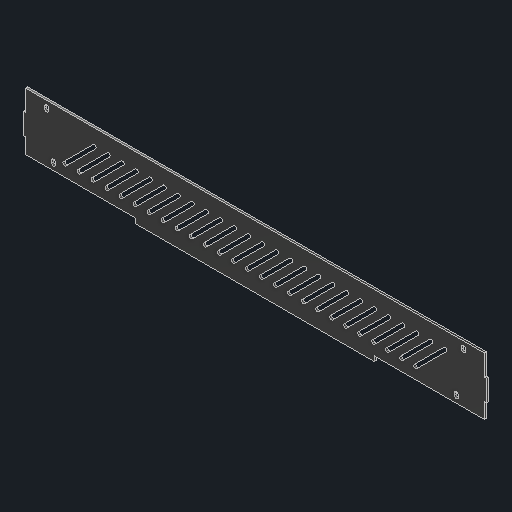
# Autodesk Inventor part: PowerBoxLengthFace
Saved by Autodesk Inventor 2027.1 (Build 311270010, 270A)
## iProperties
Created: 2026-10-13
Part Number: PowerBoxLengthFace
Material: MDF Medium Density Fiberboard
Document SubType Name: Modeling
Designer: SDS Scholar
Density: 0.8 g/cm^3
Appearance: Glossy - Black
Mass: 121.059 g
Surface Area: 1052.27 cm^2
Volume: 151.324 cm^3
Author: SDS Scholar
Autodesk Inventor part; units mm, degrees
ref_plane "YZ Plane" through (0, 0, 0) normal (1, 0, 0) x (0, 1, 0)
ref_plane "XZ Plane" through (0, 0, 0) normal (0, 1, 0) x (-1, 0, 0)
ref_plane "XY Plane" through (0, 0, 0) normal (0, 0, 1) x (1, 0, 0)
sketch "Sketch1" plane through (0, 0, 0) normal (0, 0, 1) x (1, 0, 0)
  line L0 (-330, 44.5) -> (330, 44.5)
  line L1 (330, 44.5) -> (330, -44.5)
  line L2 (330, -44.5) -> (-330, -44.5)
  line L3 (-330, -44.5) -> (-330, 44.5)
  point P0 (0, 0)
  point P1 (330, 0)
  point P2 (0, 44.5)
  dimension "d0" = 660
  dimension "d1" = 89
  constraints: 8 end point, 2 midpoint, 2 parallel, 1 horizontal, 1 horizontal alignment, 1 perpendicular, 1 vertical alignment
  measures "d0" distance of L0.start L0.end
  measures "d1" distance of L0.end L1.end
extrude "Extrusion1" add sketch "Sketch1" along normal blind 3
sketch "Sketch2" plane through (0, 0, 0) normal (0, 0, -1) x (-1, 0, 0)
  line L0 (-313.2342, 61.5305) -> (316.7658, 61.5305)
  line L1 (-310.2342, 64.5305) -> (313.7658, 64.5305)
  line L2 (316.7658, 61.5305) -> (316.7658, 64.5305)
  line L3 (316.7658, 64.5305) -> (236.7658, 64.5305)
  line L4 (236.7658, 64.5305) -> (236.7658, 61.5305)
  line L5 (236.7658, 61.5305) -> (316.7658, 61.5305)
  line L6 (316.7658, 61.5305) -> (-313.2342, 61.5305)
  line L7 (236.7658, 64.5305) -> (236.7658, 61.5305)
  line L8 (236.7658, 61.5305) -> (156.4658, 61.5305)
  line L9 (156.4658, 61.5305) -> (156.4658, 64.5305)
  line L10 (156.4658, 64.5305) -> (236.7658, 64.5305)
  line L11 (156.4658, 64.5305) -> (156.4658, 61.5305)
  line L12 (156.4658, 61.5305) -> (76.4658, 61.5305)
  line L13 (76.4658, 61.5305) -> (76.4658, 64.5305)
  line L14 (76.4658, 64.5305) -> (156.4658, 64.5305)
  line L15 (76.4658, 61.5305) -> (76.4658, 64.5305)
  line L16 (76.4658, 64.5305) -> (-3.8342, 64.5305)
  line L17 (-3.8342, 64.5305) -> (-3.8342, 61.5305)
  line L18 (-3.8342, 61.5305) -> (76.4658, 61.5305)
  line L19 (-3.8342, 64.5305) -> (-3.8342, 61.5305)
  line L20 (-3.8342, 61.5305) -> (-83.8342, 61.5305)
  line L21 (-83.8342, 61.5305) -> (-83.8342, 64.5305)
  line L22 (-83.8342, 64.5305) -> (-3.8342, 64.5305)
  line L23 (-83.8342, 64.5305) -> (-83.8342, 61.5305)
  line L24 (-83.8342, 61.5305) -> (-164.1342, 61.5305)
  line L25 (-164.1342, 61.5305) -> (-164.1342, 64.5305)
  line L26 (-164.1342, 64.5305) -> (-83.8342, 64.5305)
  line L27 (-164.1342, 64.5305) -> (-164.1342, 61.5305)
  line L28 (-164.1342, 61.5305) -> (-244.1342, 61.5305)
  line L29 (-244.1342, 61.5305) -> (-244.1342, 64.5305)
  line L30 (-244.1342, 64.5305) -> (-164.1342, 64.5305)
  line L31 (-244.1342, 64.5305) -> (-244.1342, 61.5305)
  line L32 (-244.1342, 61.5305) -> (-313.2342, 61.5305)
  line L33 (-313.2342, 61.5305) -> (-313.2342, 64.5305)
  line L34 (-313.2342, 64.5305) -> (-244.1342, 64.5305)
  line L35 (313.7658, 64.5305) -> (316.7658, 64.5305)
  line L36 (-313.2342, 61.5305) -> (-313.2342, 64.5305)
  line L37 (-310.2342, 64.5305) -> (-313.2342, 64.5305)
  line L38 (-330, 44.5) -> (-330, 47.5)
  line L39 (315, 39.5) -> (315, 42.5)
  line L40 (-330, 47.5) -> (300, 47.5)
  line L41 (-330, 47.5) -> (330, 47.5)
  line L42 (330, 47.5) -> (330, -44.5)
  line L43 (330, -44.5) -> (-330, -44.5)
  line L44 (-330, -44.5) -> (-330, 47.5)
  line L45 (-327, 44.5) -> (327, 44.5)
  line L46 (327, 44.5) -> (327, -41.5)
  line L47 (327, -41.5) -> (-327, -41.5)
  line L48 (-327, -41.5) -> (-327, 44.5)
  line L49 (330, 47.5) -> (249.7, 47.5)
  line L50 (249.7, 47.5) -> (249.7, 44.5)
  line L51 (249.7, 44.5) -> (330, 44.5)
  line L52 (330, 44.5) -> (330, 47.5)
  line L53 (249.7, 44.5) -> (169.7, 44.5)
  line L54 (169.7, 44.5) -> (169.7, 47.5)
  line L55 (169.7, 47.5) -> (249.7, 47.5)
  line L56 (249.7, 47.5) -> (249.7, 44.5)
  line L57 (169.7, 47.5) -> (89.4, 47.5)
  line L58 (89.4, 47.5) -> (89.4, 44.5)
  line L59 (89.4, 44.5) -> (169.7, 44.5)
  line L60 (169.7, 44.5) -> (169.7, 47.5)
  line L61 (89.4, 44.5) -> (9.4, 44.5)
  line L62 (9.4, 44.5) -> (9.4, 47.5)
  line L63 (9.4, 47.5) -> (89.4, 47.5)
  line L64 (89.4, 47.5) -> (89.4, 44.5)
  line L65 (9.4, 44.5) -> (-70.9, 44.5)
  line L66 (-70.9, 44.5) -> (-70.9, 47.5)
  line L67 (-70.9, 47.5) -> (9.4, 47.5)
  line L68 (9.4, 47.5) -> (9.4, 44.5)
  line L69 (-70.9, 44.5) -> (-150.9, 44.5)
  line L70 (-150.9, 44.5) -> (-150.9, 47.5)
  line L71 (-150.9, 47.5) -> (-70.9, 47.5)
  line L72 (-70.9, 47.5) -> (-70.9, 44.5)
  line L73 (-150.9, 44.5) -> (-231.2, 44.5)
  line L74 (-231.2, 44.5) -> (-231.2, 47.5)
  line L75 (-231.2, 47.5) -> (-150.9, 47.5)
  line L76 (-150.9, 47.5) -> (-150.9, 44.5)
  line L77 (-231.2, 44.5) -> (-330, 44.5)
  line L78 (-330, 44.5) -> (-330, 47.5)
  line L79 (-330, 47.5) -> (-231.2, 47.5)
  line L80 (-231.2, 47.5) -> (-231.2, 44.5)
  line L81 (-429.1643, 55.2975) -> (-429.1643, 52.2975)
  line L82 (-429.1643, 52.2975) -> (-429.1643, -26.7025)
  line L83 (-429.1643, -26.7025) -> (-429.1643, 52.2975)
  line L84 (-426.1643, -23.7025) -> (-426.1643, 52.2975)
  line L85 (-429.1643, 52.2975) -> (-426.1643, 52.2975)
  line L86 (-426.1643, 52.2975) -> (-426.1643, 21.9975)
  line L87 (-426.1643, 21.9975) -> (-429.1643, 21.9975)
  line L88 (-429.1643, 21.9975) -> (-429.1643, 52.2975)
  line L89 (-426.1643, 21.9975) -> (-429.1643, 21.9975)
  line L90 (-429.1643, 21.9975) -> (-429.1643, -8.0025)
  line L91 (-429.1643, -8.0025) -> (-426.1643, -8.0025)
  line L92 (-426.1643, -8.0025) -> (-426.1643, 21.9975)
  line L93 (-426.1643, -8.0025) -> (-429.1643, -8.0025)
  line L94 (-429.1643, -8.0025) -> (-429.1643, -26.7025)
  line L95 (-429.1643, -26.7025) -> (-426.1643, -26.7025)
  line L96 (-426.1643, -26.7025) -> (-426.1643, -8.0025)
  line L97 (-429.1643, 55.2975) -> (-426.1643, 55.2975)
  line L98 (-426.1643, 55.2975) -> (-426.1643, 52.2975)
  line L99 (-426.1643, 52.2975) -> (-429.1643, 52.2975)
  line L100 (-429.1643, 52.2975) -> (-429.1643, 55.2975)
  line L101 (-330, 44.5) -> (-327, 44.5)
  line L102 (-327, 44.5) -> (-327, 14.5)
  line L103 (-327, 14.5) -> (-330, 14.5)
  line L104 (-330, 14.5) -> (-330, 44.5)
  line L105 (-327, 14.5) -> (-330, 14.5)
  line L106 (-330, 14.5) -> (-330, -15.8)
  line L107 (-330, -15.8) -> (-327, -15.8)
  line L108 (-327, -15.8) -> (-327, 14.5)
  line L109 (-330, -15.8) -> (-327, -15.8)
  line L110 (-327, -15.8) -> (-327, -44.5)
  line L111 (-327, -44.5) -> (-330, -44.5)
  line L112 (-330, -44.5) -> (-330, -15.8)
  line L113 (327, 44.5) -> (330, 44.5)
  line L114 (330, 44.5) -> (330, 14.5)
  line L115 (330, 14.5) -> (327, 14.5)
  line L116 (327, 14.5) -> (327, 44.5)
  line L117 (327, 14.5) -> (330, 14.5)
  line L118 (330, 14.5) -> (330, -15.8)
  line L119 (330, -15.8) -> (327, -15.8)
  line L120 (327, -15.8) -> (327, 14.5)
  line L121 (327, -15.8) -> (330, -15.8)
  line L122 (330, -15.8) -> (330, -44.5)
  line L123 (330, -44.5) -> (327, -44.5)
  line L124 (327, -44.5) -> (327, -15.8)
  point P0 (0, 0)
  point P1 (1.7658, 32.3371)
  point P2 (-310.2342, 64.5305)
  point P3 (327, 44.5)
  point P4 (249.7, 47.5)
  point P5 (89.4, 47.5)
  point P6 (169.7, 44.5)
  point P7 (169.7, 47.5)
  point P8 (-70.9, 47.5)
  point P9 (-70.9, 44.5)
  point P10 (9.4, 44.5)
  point P11 (9.4, 47.5)
  point P12 (-231.2, 47.5)
  point P13 (-150.9, 44.5)
  point P14 (-289.1643, -8.0025)
  point P15 (327, -41.5)
  point P16 (327, 44.5)
  point P17 (-330, 14.5)
  point P18 (-327, 44.5)
  point P19 (-330, 44.5)
  point P20 (280, 47.5)
  point P21 (-277, 44.5)
  point P22 (-280, 44.5)
  dimension "d4" = 3
  dimension "d5" = 80
  dimension "d6" = 80.3
  dimension "d7" = 80
  dimension "d8" = 80.3
  dimension "d9" = 80
  dimension "d10" = 80.3
  dimension "d11" = 80
  dimension "d14" = 3
  dimension "d15" = 80.3
  dimension "d16" = 80
  dimension "d17" = 80.3
  dimension "d18" = 80
  dimension "d19" = 80.3
  dimension "d20" = 80
  dimension "d21" = 80.3
  dimension "d24" = 3
  dimension "d25" = 30.3
  dimension "d26" = 30
  dimension "d27" = 30
  dimension "d28" = 30.3
  dimension "d29" = 30
  dimension "d30" = 30.3
  constraints: 250 end point, 56 parallel, 28 perpendicular, 23 point on line, 20 horizontal, 3 other
  measures "d4" distance between parallel lines of L0 L1
  measures "d5" distance of L4.start L3.start
  measures "d6" distance of L7.end L9.start
  measures "d7" distance of L11.end L12.end
  measures "d8" distance of L17.start L15.end
  measures "d9" distance of L19.end L20.end
  measures "d10" distance of L24.start L24.end
  measures "d11" distance of L27.end L29.start
  measures "d14" distance between parallel lines of L44 L48
  measures "d15" distance of L51.end L50.end
  measures "d16" distance of L54.end L55.end
  measures "d17" distance of L59.end L58.end
  measures "d18" distance of L62.end L63.end
  measures "d19" distance of L66.end L67.end
  measures "d20" distance of L70.end L71.end
  measures "d21" distance of L74.end L75.end
  measures "d24" distance between parallel lines of L83 L84
  measures "d25" distance of L86.start L92.end
  measures "d26" distance of L91.start L89.end
  measures "d27" distance of L101.end L102.end
  measures "d28" distance of L106.end L105.end
  measures "d29" distance of L113.end L114.end
  measures "d30" distance of L117.end L118.end
extrude "Extrusion3" cut sketch "Sketch2" against normal blind 80.3 contours L77 L48 L103 L44 | L107 L48 L110 L43 L44 | L124 L46 L119 L42 L43 | L46 L51 L42 L115
sketch "Sketch3" plane through (0, 0, 0) normal (0, 0, -1) x (-1, 0, 0)
  line L0 (291.2132, -21.2132) -> (248.7868, 21.2132) construction
  line L1 (292.981, -19.4454) -> (250.5546, 22.981)
  line L2 (247.019, 19.4454) -> (289.4454, -22.981)
  arc A0 (289.4454, -22.981) -> (292.981, -19.4454) centre (291.2132, -21.2132) ccw
  arc A1 (250.5546, 22.981) -> (247.019, 19.4454) centre (248.7868, 21.2132) ccw
  line L3 (-315, 0) -> (315, 0)
  line L4 (227.019, 19.4454) -> (269.4454, -22.981)
  line L5 (272.981, -19.4454) -> (230.5546, 22.981)
  arc A2 (269.4454, -22.981) -> (272.981, -19.4454) centre (271.2132, -21.2132) ccw
  arc A3 (230.5546, 22.981) -> (227.019, 19.4454) centre (228.7868, 21.2132) ccw
  line L6 (271.2132, -21.2132) -> (228.7868, 21.2132) construction
  line L7 (207.019, 19.4454) -> (249.4454, -22.981)
  line L8 (252.981, -19.4454) -> (210.5546, 22.981)
  arc A4 (249.4454, -22.981) -> (252.981, -19.4454) centre (251.2132, -21.2132) ccw
  arc A5 (210.5546, 22.981) -> (207.019, 19.4454) centre (208.7868, 21.2132) ccw
  line L9 (251.2132, -21.2132) -> (208.7868, 21.2132) construction
  line L10 (187.019, 19.4454) -> (229.4454, -22.981)
  line L11 (232.981, -19.4454) -> (190.5546, 22.981)
  arc A6 (229.4454, -22.981) -> (232.981, -19.4454) centre (231.2132, -21.2132) ccw
  arc A7 (190.5546, 22.981) -> (187.019, 19.4454) centre (188.7868, 21.2132) ccw
  line L12 (231.2132, -21.2132) -> (188.7868, 21.2132) construction
  line L13 (167.019, 19.4454) -> (209.4454, -22.981)
  line L14 (212.981, -19.4454) -> (170.5546, 22.981)
  arc A8 (209.4454, -22.981) -> (212.981, -19.4454) centre (211.2132, -21.2132) ccw
  arc A9 (170.5546, 22.981) -> (167.019, 19.4454) centre (168.7868, 21.2132) ccw
  line L15 (211.2132, -21.2132) -> (168.7868, 21.2132) construction
  line L16 (147.019, 19.4454) -> (189.4454, -22.981)
  line L17 (192.981, -19.4454) -> (150.5546, 22.981)
  arc A10 (189.4454, -22.981) -> (192.981, -19.4454) centre (191.2132, -21.2132) ccw
  arc A11 (150.5546, 22.981) -> (147.019, 19.4454) centre (148.7868, 21.2132) ccw
  line L18 (191.2132, -21.2132) -> (148.7868, 21.2132) construction
  line L19 (127.019, 19.4454) -> (169.4454, -22.981)
  line L20 (172.981, -19.4454) -> (130.5546, 22.981)
  arc A12 (169.4454, -22.981) -> (172.981, -19.4454) centre (171.2132, -21.2132) ccw
  arc A13 (130.5546, 22.981) -> (127.019, 19.4454) centre (128.7868, 21.2132) ccw
  line L21 (171.2132, -21.2132) -> (128.7868, 21.2132) construction
  line L22 (107.019, 19.4454) -> (149.4454, -22.981)
  line L23 (152.981, -19.4454) -> (110.5546, 22.981)
  arc A14 (149.4454, -22.981) -> (152.981, -19.4454) centre (151.2132, -21.2132) ccw
  arc A15 (110.5546, 22.981) -> (107.019, 19.4454) centre (108.7868, 21.2132) ccw
  line L24 (151.2132, -21.2132) -> (108.7868, 21.2132) construction
  line L25 (87.019, 19.4454) -> (129.4454, -22.981)
  line L26 (132.981, -19.4454) -> (90.5546, 22.981)
  arc A16 (129.4454, -22.981) -> (132.981, -19.4454) centre (131.2132, -21.2132) ccw
  arc A17 (90.5546, 22.981) -> (87.019, 19.4454) centre (88.7868, 21.2132) ccw
  line L27 (131.2132, -21.2132) -> (88.7868, 21.2132) construction
  line L28 (67.019, 19.4454) -> (109.4454, -22.981)
  line L29 (112.981, -19.4454) -> (70.5546, 22.981)
  arc A18 (109.4454, -22.981) -> (112.981, -19.4454) centre (111.2132, -21.2132) ccw
  arc A19 (70.5546, 22.981) -> (67.019, 19.4454) centre (68.7868, 21.2132) ccw
  line L30 (111.2132, -21.2132) -> (68.7868, 21.2132) construction
  line L31 (47.019, 19.4454) -> (89.4454, -22.981)
  line L32 (92.981, -19.4454) -> (50.5546, 22.981)
  arc A20 (89.4454, -22.981) -> (92.981, -19.4454) centre (91.2132, -21.2132) ccw
  arc A21 (50.5546, 22.981) -> (47.019, 19.4454) centre (48.7868, 21.2132) ccw
  line L33 (91.2132, -21.2132) -> (48.7868, 21.2132) construction
  line L34 (27.019, 19.4454) -> (69.4454, -22.981)
  line L35 (72.981, -19.4454) -> (30.5546, 22.981)
  arc A22 (69.4454, -22.981) -> (72.981, -19.4454) centre (71.2132, -21.2132) ccw
  arc A23 (30.5546, 22.981) -> (27.019, 19.4454) centre (28.7868, 21.2132) ccw
  line L36 (71.2132, -21.2132) -> (28.7868, 21.2132) construction
  line L37 (7.019, 19.4454) -> (49.4454, -22.981)
  line L38 (52.981, -19.4454) -> (10.5546, 22.981)
  arc A24 (49.4454, -22.981) -> (52.981, -19.4454) centre (51.2132, -21.2132) ccw
  arc A25 (10.5546, 22.981) -> (7.019, 19.4454) centre (8.7868, 21.2132) ccw
  line L39 (51.2132, -21.2132) -> (8.7868, 21.2132) construction
  line L40 (-12.981, 19.4454) -> (29.4454, -22.981)
  line L41 (32.981, -19.4454) -> (-9.4454, 22.981)
  arc A26 (29.4454, -22.981) -> (32.981, -19.4454) centre (31.2132, -21.2132) ccw
  arc A27 (-9.4454, 22.981) -> (-12.981, 19.4454) centre (-11.2132, 21.2132) ccw
  line L42 (31.2132, -21.2132) -> (-11.2132, 21.2132) construction
  line L43 (-32.981, 19.4454) -> (9.4454, -22.981)
  line L44 (12.981, -19.4454) -> (-29.4454, 22.981)
  arc A28 (9.4454, -22.981) -> (12.981, -19.4454) centre (11.2132, -21.2132) ccw
  arc A29 (-29.4454, 22.981) -> (-32.981, 19.4454) centre (-31.2132, 21.2132) ccw
  line L45 (11.2132, -21.2132) -> (-31.2132, 21.2132) construction
  line L46 (-52.981, 19.4454) -> (-10.5546, -22.981)
  line L47 (-7.019, -19.4454) -> (-49.4454, 22.981)
  arc A30 (-10.5546, -22.981) -> (-7.019, -19.4454) centre (-8.7868, -21.2132) ccw
  arc A31 (-49.4454, 22.981) -> (-52.981, 19.4454) centre (-51.2132, 21.2132) ccw
  line L48 (-8.7868, -21.2132) -> (-51.2132, 21.2132) construction
  line L49 (-72.981, 19.4454) -> (-30.5546, -22.981)
  line L50 (-27.019, -19.4454) -> (-69.4454, 22.981)
  arc A32 (-30.5546, -22.981) -> (-27.019, -19.4454) centre (-28.7868, -21.2132) ccw
  arc A33 (-69.4454, 22.981) -> (-72.981, 19.4454) centre (-71.2132, 21.2132) ccw
  line L51 (-28.7868, -21.2132) -> (-71.2132, 21.2132) construction
  line L52 (-92.981, 19.4454) -> (-50.5546, -22.981)
  line L53 (-47.019, -19.4454) -> (-89.4454, 22.981)
  arc A34 (-50.5546, -22.981) -> (-47.019, -19.4454) centre (-48.7868, -21.2132) ccw
  arc A35 (-89.4454, 22.981) -> (-92.981, 19.4454) centre (-91.2132, 21.2132) ccw
  line L54 (-48.7868, -21.2132) -> (-91.2132, 21.2132) construction
  line L55 (-112.981, 19.4454) -> (-70.5546, -22.981)
  line L56 (-67.019, -19.4454) -> (-109.4454, 22.981)
  arc A36 (-70.5546, -22.981) -> (-67.019, -19.4454) centre (-68.7868, -21.2132) ccw
  arc A37 (-109.4454, 22.981) -> (-112.981, 19.4454) centre (-111.2132, 21.2132) ccw
  line L57 (-68.7868, -21.2132) -> (-111.2132, 21.2132) construction
  line L58 (-132.981, 19.4454) -> (-90.5546, -22.981)
  line L59 (-87.019, -19.4454) -> (-129.4454, 22.981)
  arc A38 (-90.5546, -22.981) -> (-87.019, -19.4454) centre (-88.7868, -21.2132) ccw
  arc A39 (-129.4454, 22.981) -> (-132.981, 19.4454) centre (-131.2132, 21.2132) ccw
  line L60 (-88.7868, -21.2132) -> (-131.2132, 21.2132) construction
  line L61 (-152.981, 19.4454) -> (-110.5546, -22.981)
  line L62 (-107.019, -19.4454) -> (-149.4454, 22.981)
  arc A40 (-110.5546, -22.981) -> (-107.019, -19.4454) centre (-108.7868, -21.2132) ccw
  arc A41 (-149.4454, 22.981) -> (-152.981, 19.4454) centre (-151.2132, 21.2132) ccw
  line L63 (-108.7868, -21.2132) -> (-151.2132, 21.2132) construction
  line L64 (-172.981, 19.4454) -> (-130.5546, -22.981)
  line L65 (-127.019, -19.4454) -> (-169.4454, 22.981)
  arc A42 (-130.5546, -22.981) -> (-127.019, -19.4454) centre (-128.7868, -21.2132) ccw
  arc A43 (-169.4454, 22.981) -> (-172.981, 19.4454) centre (-171.2132, 21.2132) ccw
  line L66 (-128.7868, -21.2132) -> (-171.2132, 21.2132) construction
  line L67 (-192.981, 19.4454) -> (-150.5546, -22.981)
  line L68 (-147.019, -19.4454) -> (-189.4454, 22.981)
  arc A44 (-150.5546, -22.981) -> (-147.019, -19.4454) centre (-148.7868, -21.2132) ccw
  arc A45 (-189.4454, 22.981) -> (-192.981, 19.4454) centre (-191.2132, 21.2132) ccw
  line L69 (-148.7868, -21.2132) -> (-191.2132, 21.2132) construction
  line L70 (-212.981, 19.4454) -> (-170.5546, -22.981)
  line L71 (-167.019, -19.4454) -> (-209.4454, 22.981)
  arc A46 (-170.5546, -22.981) -> (-167.019, -19.4454) centre (-168.7868, -21.2132) ccw
  arc A47 (-209.4454, 22.981) -> (-212.981, 19.4454) centre (-211.2132, 21.2132) ccw
  line L72 (-168.7868, -21.2132) -> (-211.2132, 21.2132) construction
  line L73 (-232.981, 19.4454) -> (-190.5546, -22.981)
  line L74 (-187.019, -19.4454) -> (-229.4454, 22.981)
  arc A48 (-190.5546, -22.981) -> (-187.019, -19.4454) centre (-188.7868, -21.2132) ccw
  arc A49 (-229.4454, 22.981) -> (-232.981, 19.4454) centre (-231.2132, 21.2132) ccw
  line L75 (-188.7868, -21.2132) -> (-231.2132, 21.2132) construction
  line L76 (-252.981, 19.4454) -> (-210.5546, -22.981)
  line L77 (-207.019, -19.4454) -> (-249.4454, 22.981)
  arc A50 (-210.5546, -22.981) -> (-207.019, -19.4454) centre (-208.7868, -21.2132) ccw
  arc A51 (-249.4454, 22.981) -> (-252.981, 19.4454) centre (-251.2132, 21.2132) ccw
  line L78 (-208.7868, -21.2132) -> (-251.2132, 21.2132) construction
  line L79 (-272.981, 19.4454) -> (-230.5546, -22.981)
  line L80 (-227.019, -19.4454) -> (-269.4454, 22.981)
  arc A52 (-230.5546, -22.981) -> (-227.019, -19.4454) centre (-228.7868, -21.2132) ccw
  arc A53 (-269.4454, 22.981) -> (-272.981, 19.4454) centre (-271.2132, 21.2132) ccw
  line L81 (-228.7868, -21.2132) -> (-271.2132, 21.2132) construction
  line L82 (-292.981, 19.4454) -> (-250.5546, -22.981)
  line L83 (-247.019, -19.4454) -> (-289.4454, 22.981)
  arc A54 (-250.5546, -22.981) -> (-247.019, -19.4454) centre (-248.7868, -21.2132) ccw
  arc A55 (-289.4454, 22.981) -> (-292.981, 19.4454) centre (-291.2132, 21.2132) ccw
  line L84 (-248.7868, -21.2132) -> (-291.2132, 21.2132) construction
  line L85 (330, 14.5) -> (330, -15.8) projected
  point P0 (0, 0)
  point P1 (270, 0)
  point P2 (266.4645, 0)
  point P3 (273.5355, 0)
  point P4 (-273.5355, 0)
  point P5 (-266.4645, 0)
  dimension "d33" = 5
  dimension "d34" = 60
  dimension "d35" = 135
  dimension "d39" = 20
  dimension "d93" = 15
  constraints: 226 end point, 112 point on circle, 56 centre point, 4 tangent, 2 horizontal, 2 midpoint, 1 parallel, 1 point on line, 297 other
  measures "d33" diameter of A1
  measures "d34" distance of L0.start L0.end
  measures "d35" angle of L3 L0
  measures "d39" distance of L2.start L4.start
  measures "d93" distance from line of L85 L3.end
extrude "Extrusion4" cut sketch "Sketch3" against normal blind 10 contours L80 A52 L79 L3 | L3 L79 A53 L80 | L77 A50 L76 L3 | L3 L76 A51 L77 | L74 A48 L73 L3 | L3 L73 A49 L74 | L71 A46 L70 L3 | L3 L70 A47 L71 | L68 A44 L67 L3 | L3 L67 A45 L68 | L65 A42 L64 L3 | L3 L64 A43 L65 | L62 A40 L61 L3 | L3 L61 A41 L62 | L59 A38 L58 L3 | L3 L58 A39 L59 | L56 A36 L55 L3 | L3 L55 A37 L56 | L53 A34 L52 L3 | L3 L52 A35 L53 | L50 A32 L49 L3 | L3 L49 A33 L50 | L47 A30 L46 L3 | L3 L46 A31 L47 | L44 A28 L43 L3 | L3 L43 A29 L44 | L41 A26 L40 L3 | L3 L40 A27 L41 | L38 A24 L37 L3 | L3 L37 A25 L38 | L35 A22 L34 L3 | L3 L34 A23 L35 | L32 A20 L31 L3 | L3 L31 A21 L32 | L29 A18 L28 L3 | L3 L28 A19 L29 | L26 A16 L25 L3 | L3 L25 A17 L26 | L23 A14 L22 L3 | L3 L22 A15 L23 | L20 A12 L19 L3 | L3 L19 A13 L20 | L17 A10 L16 L3 | L3 L16 A11 L17 | L14 A8 L13 L3 | L3 L13 A9 L14 | L11 A6 L10 L3 | L3 L10 A7 L11 | L8 A4 L7 L3 | L3 L7 A5 L8 | L5 A2 L4 L3 | L3 L4 A3 L5
sketch "Sketch4" plane through (0, 0, 3) normal (0, 0, 1) x (1, 0, 0)
  line L0 (-327, -44.5) -> (327, -44.5) projected
  line L1 (330, -15.8) -> (330, 14.5) projected
  line L2 (327, 44.5) -> (-327, 44.5) projected
  line L3 (-330, 14.5) -> (-330, -15.8) projected
  line L4 (327, -15.8) -> (330, -15.8) projected
  line L5 (330, 14.5) -> (327, 14.5) projected
  line L6 (327, 14.5) -> (327, 44.5) projected
  line L7 (-327, 44.5) -> (-327, 14.5) projected
  line L8 (-327, 14.5) -> (-330, 14.5) projected
  line L9 (-330, -15.8) -> (-327, -15.8) projected
  line L10 (-327, -15.8) -> (-327, -44.5) projected
  line L11 (327, -44.5) -> (327, -15.8) projected
  line L12 (-327, -44.5) -> (327, -44.5)
  line L13 (327, -44.5) -> (327, -37.5)
  line L14 (327, -37.5) -> (-327, -37.5)
  line L15 (-327, -37.5) -> (-327, -44.5)
  line L16 (-327, -44.5) -> (327, -44.5) projected
  line L17 (-170.15, -37.5) -> (170.15, -37.5)
  line L18 (170.15, -37.5) -> (170.15, -44.5)
  line L19 (170.15, -44.5) -> (-170.15, -44.5)
  line L20 (-170.15, -44.5) -> (-170.15, -37.5)
  point P0 (0, 0)
  point P1 (0, -44.5)
  point P2 (0, -44.5)
  point P3 (170.15, -37.5)
  point P4 (-170.15, -44.5)
  dimension "d82" = 7
  dimension "d83" = 340.3
  constraints: 16 end point, 4 parallel, 3 point on line, 2 horizontal, 2 midpoint, 2 perpendicular, 1 coincident
  measures "d82" distance of L13.end L12.end
  measures "d83" distance of L18.end L19.end
extrude "Extrusion5" cut sketch "Sketch4" against normal through all contours L10 L14 L20 L0 | L18 L14 L11 L0
sketch "Sketch5" plane through (0, 0, 3) normal (0, 0, 1) x (1, 0, 0)
  line L0 (330, -15.8) -> (330, 14.5) projected
  line L1 (-297, 36) -> (-297, 33) construction
  line L2 (-299.9, 36) -> (-299.9, 33)
  line L3 (-294.1, 33) -> (-294.1, 36)
  arc A0 (-294.1, 36) -> (-299.9, 36) centre (-297, 36) ccw
  arc A1 (-299.9, 33) -> (-294.1, 33) centre (-297, 33) ccw
  line L4 (297, 36) -> (297, 33) construction
  line L5 (294.1, 36) -> (294.1, 33)
  line L6 (299.9, 33) -> (299.9, 36)
  arc A2 (299.9, 36) -> (294.1, 36) centre (297, 36) ccw
  arc A3 (294.1, 33) -> (299.9, 33) centre (297, 33) ccw
  line L7 (170.15, -37.5) -> (327, -37.5) projected
  line L8 (327, -37.5) -> (327, -15.8) projected
  line L9 (327, -15.8) -> (330, -15.8) projected
  line L10 (330, -15.8) -> (330, 14.5) projected
  line L11 (330, 14.5) -> (327, 14.5) projected
  line L12 (327, 14.5) -> (327, 44.5) projected
  line L13 (327, 44.5) -> (-327, 44.5) projected
  line L14 (-327, 44.5) -> (-327, 14.5) projected
  line L15 (-327, 14.5) -> (-330, 14.5) projected
  line L16 (-330, 14.5) -> (-330, -15.8) projected
  line L17 (-330, -15.8) -> (-327, -15.8) projected
  line L18 (-327, -15.8) -> (-327, -37.5) projected
  line L19 (-327, -37.5) -> (-170.15, -37.5) projected
  line L20 (-170.15, -37.5) -> (-170.15, -44.5) projected
  line L21 (-170.15, -44.5) -> (170.15, -44.5) projected
  line L22 (170.15, -44.5) -> (170.15, -37.5) projected
  arc A4 (-187.019, 19.4454) -> (-190.5546, 22.981) centre (-188.7868, 21.2132) ccw projected
  line L23 (-187.019, 19.4454) -> (-229.4454, -22.981) projected
  arc A5 (-232.981, -19.4454) -> (-229.4454, -22.981) centre (-231.2132, -21.2132) ccw projected
  line L24 (-232.981, -19.4454) -> (-190.5546, 22.981) projected
  arc A6 (-87.019, 19.4454) -> (-90.5546, 22.981) centre (-88.7868, 21.2132) ccw projected
  line L25 (-87.019, 19.4454) -> (-129.4454, -22.981) projected
  arc A7 (-132.981, -19.4454) -> (-129.4454, -22.981) centre (-131.2132, -21.2132) ccw projected
  line L26 (-132.981, -19.4454) -> (-90.5546, 22.981) projected
  arc A8 (-27.019, 19.4454) -> (-30.5546, 22.981) centre (-28.7868, 21.2132) ccw projected
  line L27 (-27.019, 19.4454) -> (-69.4454, -22.981) projected
  arc A9 (-72.981, -19.4454) -> (-69.4454, -22.981) centre (-71.2132, -21.2132) ccw projected
  line L28 (-72.981, -19.4454) -> (-30.5546, 22.981) projected
  arc A10 (7.019, -19.4454) -> (10.5546, -22.981) centre (8.7868, -21.2132) ccw projected
  line L29 (7.019, -19.4454) -> (49.4454, 22.981) projected
  arc A11 (52.981, 19.4454) -> (49.4454, 22.981) centre (51.2132, 21.2132) ccw projected
  line L30 (52.981, 19.4454) -> (10.5546, -22.981) projected
  arc A12 (87.019, -19.4454) -> (90.5546, -22.981) centre (88.7868, -21.2132) ccw projected
  line L31 (87.019, -19.4454) -> (129.4454, 22.981) projected
  arc A13 (132.981, 19.4454) -> (129.4454, 22.981) centre (131.2132, 21.2132) ccw projected
  line L32 (132.981, 19.4454) -> (90.5546, -22.981) projected
  arc A14 (167.019, -19.4454) -> (170.5546, -22.981) centre (168.7868, -21.2132) ccw projected
  line L33 (167.019, -19.4454) -> (209.4454, 22.981) projected
  arc A15 (212.981, 19.4454) -> (209.4454, 22.981) centre (211.2132, 21.2132) ccw projected
  line L34 (212.981, 19.4454) -> (170.5546, -22.981) projected
  arc A16 (227.019, -19.4454) -> (230.5546, -22.981) centre (228.7868, -21.2132) ccw projected
  line L35 (227.019, -19.4454) -> (269.4454, 22.981) projected
  arc A17 (272.981, 19.4454) -> (269.4454, 22.981) centre (271.2132, 21.2132) ccw projected
  line L36 (272.981, 19.4454) -> (230.5546, -22.981) projected
  arc A18 (147.019, -19.4454) -> (150.5546, -22.981) centre (148.7868, -21.2132) ccw projected
  line L37 (147.019, -19.4454) -> (189.4454, 22.981) projected
  arc A19 (192.981, 19.4454) -> (189.4454, 22.981) centre (191.2132, 21.2132) ccw projected
  line L38 (192.981, 19.4454) -> (150.5546, -22.981) projected
  arc A20 (67.019, -19.4454) -> (70.5546, -22.981) centre (68.7868, -21.2132) ccw projected
  line L39 (67.019, -19.4454) -> (109.4454, 22.981) projected
  arc A21 (112.981, 19.4454) -> (109.4454, 22.981) centre (111.2132, 21.2132) ccw projected
  line L40 (112.981, 19.4454) -> (70.5546, -22.981) projected
  arc A22 (-12.981, -19.4454) -> (-9.4454, -22.981) centre (-11.2132, -21.2132) ccw projected
  line L41 (-12.981, -19.4454) -> (29.4454, 22.981) projected
  arc A23 (32.981, 19.4454) -> (29.4454, 22.981) centre (31.2132, 21.2132) ccw projected
  line L42 (32.981, 19.4454) -> (-9.4454, -22.981) projected
  arc A24 (-47.019, 19.4454) -> (-50.5546, 22.981) centre (-48.7868, 21.2132) ccw projected
  line L43 (-47.019, 19.4454) -> (-89.4454, -22.981) projected
  arc A25 (-92.981, -19.4454) -> (-89.4454, -22.981) centre (-91.2132, -21.2132) ccw projected
  line L44 (-92.981, -19.4454) -> (-50.5546, 22.981) projected
  arc A26 (-107.019, 19.4454) -> (-110.5546, 22.981) centre (-108.7868, 21.2132) ccw projected
  line L45 (-107.019, 19.4454) -> (-149.4454, -22.981) projected
  arc A27 (-152.981, -19.4454) -> (-149.4454, -22.981) centre (-151.2132, -21.2132) ccw projected
  line L46 (-152.981, -19.4454) -> (-110.5546, 22.981) projected
  arc A28 (-207.019, 19.4454) -> (-210.5546, 22.981) centre (-208.7868, 21.2132) ccw projected
  line L47 (-207.019, 19.4454) -> (-249.4454, -22.981) projected
  arc A29 (-252.981, -19.4454) -> (-249.4454, -22.981) centre (-251.2132, -21.2132) ccw projected
  line L48 (-252.981, -19.4454) -> (-210.5546, 22.981) projected
  arc A30 (-167.019, 19.4454) -> (-170.5546, 22.981) centre (-168.7868, 21.2132) ccw projected
  line L49 (-167.019, 19.4454) -> (-209.4454, -22.981) projected
  arc A31 (-212.981, -19.4454) -> (-209.4454, -22.981) centre (-211.2132, -21.2132) ccw projected
  line L50 (-212.981, -19.4454) -> (-170.5546, 22.981) projected
  arc A32 (-127.019, 19.4454) -> (-130.5546, 22.981) centre (-128.7868, 21.2132) ccw projected
  line L51 (-127.019, 19.4454) -> (-169.4454, -22.981) projected
  arc A33 (-172.981, -19.4454) -> (-169.4454, -22.981) centre (-171.2132, -21.2132) ccw projected
  line L52 (-172.981, -19.4454) -> (-130.5546, 22.981) projected
  arc A34 (-7.019, 19.4454) -> (-10.5546, 22.981) centre (-8.7868, 21.2132) ccw projected
  line L53 (-7.019, 19.4454) -> (-49.4454, -22.981) projected
  arc A35 (-52.981, -19.4454) -> (-49.4454, -22.981) centre (-51.2132, -21.2132) ccw projected
  line L54 (-52.981, -19.4454) -> (-10.5546, 22.981) projected
  arc A36 (27.019, -19.4454) -> (30.5546, -22.981) centre (28.7868, -21.2132) ccw projected
  line L55 (27.019, -19.4454) -> (69.4454, 22.981) projected
  arc A37 (72.981, 19.4454) -> (69.4454, 22.981) centre (71.2132, 21.2132) ccw projected
  line L56 (72.981, 19.4454) -> (30.5546, -22.981) projected
  arc A38 (107.019, -19.4454) -> (110.5546, -22.981) centre (108.7868, -21.2132) ccw projected
  line L57 (107.019, -19.4454) -> (149.4454, 22.981) projected
  arc A39 (152.981, 19.4454) -> (149.4454, 22.981) centre (151.2132, 21.2132) ccw projected
  line L58 (152.981, 19.4454) -> (110.5546, -22.981) projected
  arc A40 (187.019, -19.4454) -> (190.5546, -22.981) centre (188.7868, -21.2132) ccw projected
  line L59 (187.019, -19.4454) -> (229.4454, 22.981) projected
  arc A41 (232.981, 19.4454) -> (229.4454, 22.981) centre (231.2132, 21.2132) ccw projected
  line L60 (232.981, 19.4454) -> (190.5546, -22.981) projected
  arc A42 (207.019, -19.4454) -> (210.5546, -22.981) centre (208.7868, -21.2132) ccw projected
  line L61 (207.019, -19.4454) -> (249.4454, 22.981) projected
  arc A43 (252.981, 19.4454) -> (249.4454, 22.981) centre (251.2132, 21.2132) ccw projected
  line L62 (252.981, 19.4454) -> (210.5546, -22.981) projected
  arc A44 (127.019, -19.4454) -> (130.5546, -22.981) centre (128.7868, -21.2132) ccw projected
  line L63 (127.019, -19.4454) -> (169.4454, 22.981) projected
  arc A45 (172.981, 19.4454) -> (169.4454, 22.981) centre (171.2132, 21.2132) ccw projected
  line L64 (172.981, 19.4454) -> (130.5546, -22.981) projected
  arc A46 (47.019, -19.4454) -> (50.5546, -22.981) centre (48.7868, -21.2132) ccw projected
  line L65 (47.019, -19.4454) -> (89.4454, 22.981) projected
  arc A47 (92.981, 19.4454) -> (89.4454, 22.981) centre (91.2132, 21.2132) ccw projected
  line L66 (92.981, 19.4454) -> (50.5546, -22.981) projected
  arc A48 (12.981, 19.4454) -> (9.4454, 22.981) centre (11.2132, 21.2132) ccw projected
  line L67 (12.981, 19.4454) -> (-29.4454, -22.981) projected
  arc A49 (-32.981, -19.4454) -> (-29.4454, -22.981) centre (-31.2132, -21.2132) ccw projected
  line L68 (-32.981, -19.4454) -> (9.4454, 22.981) projected
  arc A50 (-67.019, 19.4454) -> (-70.5546, 22.981) centre (-68.7868, 21.2132) ccw projected
  line L69 (-67.019, 19.4454) -> (-109.4454, -22.981) projected
  arc A51 (-112.981, -19.4454) -> (-109.4454, -22.981) centre (-111.2132, -21.2132) ccw projected
  line L70 (-112.981, -19.4454) -> (-70.5546, 22.981) projected
  arc A52 (-147.019, 19.4454) -> (-150.5546, 22.981) centre (-148.7868, 21.2132) ccw projected
  line L71 (-147.019, 19.4454) -> (-189.4454, -22.981) projected
  arc A53 (-192.981, -19.4454) -> (-189.4454, -22.981) centre (-191.2132, -21.2132) ccw projected
  line L72 (-192.981, -19.4454) -> (-150.5546, 22.981) projected
  arc A54 (-227.019, 19.4454) -> (-230.5546, 22.981) centre (-228.7868, 21.2132) ccw projected
  line L73 (-227.019, 19.4454) -> (-269.4454, -22.981) projected
  arc A55 (-272.981, -19.4454) -> (-269.4454, -22.981) centre (-271.2132, -21.2132) ccw projected
  line L74 (-272.981, -19.4454) -> (-230.5546, 22.981) projected
  line L75 (-287, -29) -> (-287, -26) construction
  line L76 (-284.1, -29) -> (-284.1, -26)
  line L77 (-289.9, -26) -> (-289.9, -29)
  arc A56 (-289.9, -29) -> (-284.1, -29) centre (-287, -29) ccw
  arc A57 (-284.1, -26) -> (-289.9, -26) centre (-287, -26) ccw
  line L78 (-170.15, -44.5) -> (170.15, -44.5) projected
  line L79 (0, -44.5) -> (0, 44.5) construction
  line L80 (287, -29) -> (287, -26) construction
  line L81 (284.1, -29) -> (284.1, -26)
  line L82 (289.9, -26) -> (289.9, -29)
  arc A58 (284.1, -29) -> (289.9, -29) centre (287, -29) ccw
  arc A59 (289.9, -26) -> (284.1, -26) centre (287, -26) ccw
  point P0 (0, 0)
  point P1 (-297, 34.5)
  point P2 (297, 34.5)
  point P3 (-287, -27.5)
  point P4 (287, -27.5)
  dimension "d72" = 3
  dimension "d73" = 5.8
  dimension "d75" = 3
  dimension "d76" = 5.8
  dimension "d85" = 8.5
  dimension "d86" = 30
  dimension "d87" = 30
  dimension "d88" = 8.5
  dimension "d89" = 3
  dimension "d90" = 5.8
  dimension "d91" = 8.5
  dimension "d92" = 40
  constraints: 34 end point, 16 point on circle, 12 tangent, 8 centre point, 7 symmetric about line, 5 midpoint, 3 parallel, 3 vertical, 2 other
  measures "d72" distance of L1.start L1.end
  measures "d73" diameter of A1
  measures "d75" distance of L4.start L4.end
  measures "d76" diameter of A3
  measures "d85" distance from line of L13 L1.start
  measures "d86" distance between parallel lines of L14 L1
  measures "d87" distance between parallel lines of L12 L4
  measures "d88" distance from line of L13 L4.start
  measures "d89" distance of L75.start L75.end
  measures "d90" diameter of A57
  measures "d91" distance from line of L19 L75.start
  measures "d92" distance between parallel lines of L75 L18
extrude "Extrusion6" cut sketch "Sketch5" against normal through all contours A0 L3 A1 L2 | A2 L6 A3 L5 | A56 L77 A57 L76 | L81 A59 L82 A58
fillet "Fillet1" [suppressed]
equation "\"d0\" = PowerBoxLength"
equation "\"d31\" = d15"
equation "\"GridProcutClearance\" = 5"
equation "\"GridBorderThickness\" = 5"
equation "\"GridBorderFillets\" = 7"
equation "\"GridTotalSize\" = 65"
equation "\"GridRobotClearance\" = 65"
equation "\"AluminiumExtrusionClearance\" = 35"
equation "\"BaseTotalLength\" = 885"
equation "\"WorkspaceLength\" = 515"
equation "\"WorkspaceHeight\" = 183"
equation "\"AxesBaseFillet\" = 15"
equation "\"Zaxis\" = 197"
equation "\"ProductTotalHeight\" = 45"
equation "\"VerticalStroke\" = 105"
equation "\"BackArea\" = 165"
equation "\"CylinderStroke\" = 75"
equation "\"BoxesWidth\" = 125"
equation "\"PowerBoxLength\" = 660"
equation "\"BaseWoodThickness\" = 7"
equation "\"kerf\" = 1.5"
equation "\"Kerf\" = 0.3"
equation "\"RxThickness\" = 1.8"
equation "\"support_2\" = 265"
body "Solid1"
